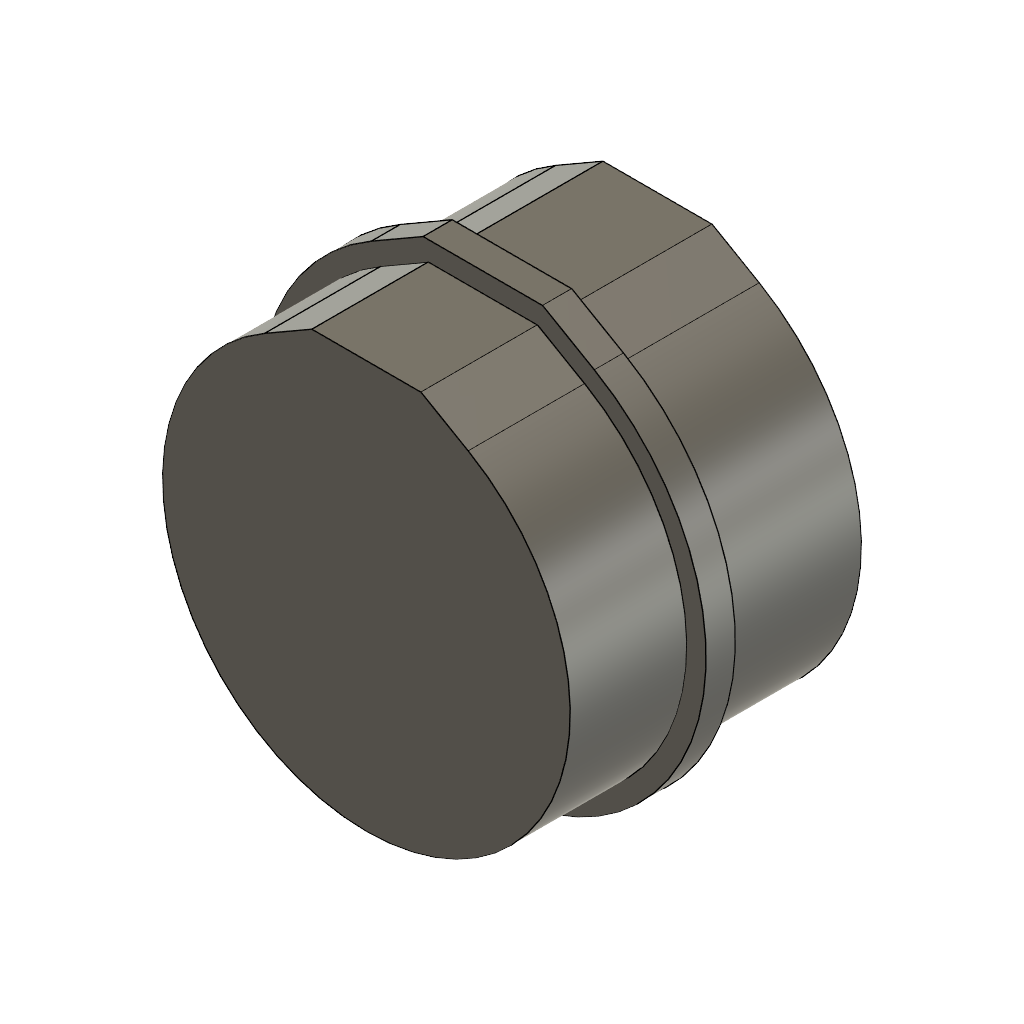
replica_ecas (Autodesk Fusion 360 design; units mm, degrees)
part number: 2026-11-10-15-27-33-977
Autodesk Fusion 360 part; units mm, degrees
ref_plane "WorkPlane1" through (0, 0, 23.05) normal (0, 0, 1) x (1, 0, 0)
sketch "Sketch1" plane through (0, 0, 23.05) normal (0, 0, 1) x (1, 0, 0)
  line L0 (-17.8431, 20) -> (-27.5, 10.3431)
  arc A0 (-27.5, 6.3199) -> (-26.3302, 3.1059) centre (-22.5, 6.3199) ccw
  line L1 (-26.3302, 3.1059) -> (-20.5096, -3.8308)
  arc A1 (-20.5096, -3.8308) -> (-20.2023, -4.1741) centre (-15, 0.7923) ccw
  spline S0 degree 3 poles (-15, -12.3777) (-15, -11.8756) (-15.1011, -11.391) (-15.518, -10.2882) (-15.8904, -9.6934) (-16.8948, -8.3522) (-17.5903, -7.5923) (-18.9478, -5.9881) (-19.6232, -5.1384) (-20.2023, -4.1741) knots 0 0 0 0 0.150622 0.150622 0.352713 0.352713 0.618566 0.618566 0.862231 0.862231 0.862231 0.862231
  line L2 (-15, -12.3777) -> (-15, -15)
  line L3 (-15, -15) -> (15, -15)
  line L4 (15, -15) -> (15, -12.3777)
  spline S1 degree 3 poles (20.2023, -4.1741) (19.4898, -5.3606) (18.6277, -6.379) (17.0639, -8.1888) (16.3407, -9.0062) (15.5692, -10.2511) (15.3569, -10.6701) (15.075, -11.5247) (15, -11.9454) (15, -12.3777) knots 0 0 0 0 0.415181 0.415181 0.816478 0.816478 1.004003 1.004003 1.177971 1.177971 1.177971 1.177971
  arc A2 (20.2023, -4.1741) -> (20.5096, -3.8308) centre (15, 0.7923) ccw
  line L5 (20.5096, -3.8308) -> (26.3302, 3.1059)
  arc A3 (26.3302, 3.1059) -> (27.5, 6.3199) centre (22.5, 6.3199) ccw
  line L6 (27.5, 10.3431) -> (17.8431, 20)
  line L7 (17.8431, 20) -> (-17.8431, 20)
  circle A4 centre (0, 4.3) radius 4.2
  circle A5 centre (0, 4.3) radius 4.6
  line L8 (-2.1, 7.9373) -> (-1.1254, 8.5)
  line L9 (-1.1254, 8.5) -> (1.1254, 8.5)
  line L10 (1.1254, 8.5) -> (2.1, 7.9373)
  line L11 (-2.3, 8.2837) -> (-1.2326, 8.9)
  line L12 (-1.2326, 8.9) -> (1.2326, 8.9)
  line L13 (1.2326, 8.9) -> (2.3, 8.2837)
  line L14 (0, 6.7826) -> (1.075, 6.162)
  arc A6 (-1.075, 6.162) -> (1.075, 6.162) centre (0, 4.3) ccw
  line L15 (-1.075, 6.162) -> (0, 6.7826)
  line L16 (-27.5, 10.3431) -> (-27.5, 6.3199)
  line L17 (27.5, 6.3199) -> (27.5, 10.3431)
extrude "Extrusion1" add sketch "Sketch1" against normal blind 2.4 contours A4 | A4 L9 L10 | A4 L8 L9 | L14 A6 L15
extrude "Extrusion2" add sketch "Sketch1" against normal blind 0.6 from surface at -2.4 contours A4 | A4 L9 L10 | A4 L8 L9 | A5 | A5 L12 L13 | A5 L11 L12 | L14 A6 L15
extrude "Extrusion3" add sketch "Sketch1" against normal blind 3 from surface at -3 contours A4 | A4 L9 L10 | A4 L8 L9 | L14 A6 L15
equation "hotend_length = 54 mm" comment "Lenght of the uhf hotend for the uhf cowls. Default: 54mm  (Pheatus dragon UHF alike)"
equation "hotend_screwhole_radius = 8.1 mm" comment "Radius of the mounting screholes. Default: 8,10mm (pheatus dragon alike)"
equation "hotend_diameter = 22.2 mm" comment "Diameter of the kotend heatsink. Default: 22,20mm (pheatus dragon alike)"
equation "DS_adapter_lenght = 35.75 mm" comment "Lenght or depth of the DraftShift adapter. Default: 35,75m"
equation "extruder_screwholes_right = 17.5 mm" comment "Right extruder screwhole, distance from center. Orbiter:  17,5 Sherpa_mini:  21,75 Sherpa_micro:  18.05"
equation "extruder_screwholes_left = 19.5 mm" comment "Left extruder screwhole, distance from center. Orbiter:  16,5 Sherpa_mini:  21,75 Sherpa_micro:  13,95"
equation "heat_insert_diameter = 4.5 mm" comment "Diameter of the M3 heated inserts holes, Default: 4.5mm"
